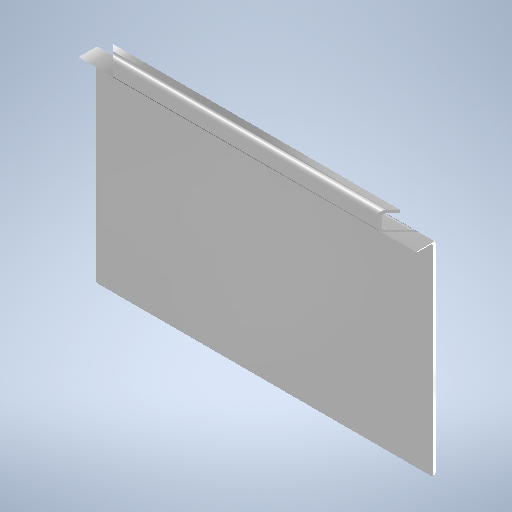
# Autodesk Inventor part: CHAPA 18 DE ACO INOX-304 - TAMPA DE FECHAMENTO DA CAIXA
Saved by Autodesk Inventor 2025 (Build 290162000, 162)
## iProperties
Created: 2019-07-12
Part Number: CHAPA 18 DE ACO INOX-304 - TAMPA DE FECHAMENTO DA CAIXA
Material: Aço inoxidável AISI 304
Document SubType Name: Chapa
Designer: CESAR
Density: 8 g/cm^3
Flat Pattern Width: 10.8343 cm
Flat Pattern Length: 14.88 cm
Flat Pattern Area: 161.214 cm^2
Sheet Metal Rule: Default_mm
Sheet Metal Width: 108,343 mm
Sheet Metal Length: 148,800 mm
Sheet Metal Area: 16121,440 mm^2
Appearance: Cromo - Acetinado
Mass: 609.333 g
Surface Area: 1281.93 cm^2
Volume: 76.1666 cm^3
Author: CESAR
Autodesk Inventor part; units mm, degrees
ref_plane "YZ Plane" through (0, 0, 0) normal (1, 0, 0) x (0, 1, 0)
ref_plane "XZ Plane" through (0, 0, 0) normal (0, 1, 0) x (-1, 0, 0)
ref_plane "XY Plane" through (0, 0, 0) normal (0, 0, 1) x (1, 0, 0)
sketch "Esboço1" plane through (0, 0, 0) normal (0, 1, 0) x (-1, 0, 0)
  line L0 (-74.4, 44.7) -> (74.4, 44.7)
  line L1 (74.4, 44.7) -> (74.4, -44.7)
  line L2 (74.4, -44.7) -> (-74.4, -44.7)
  line L3 (-74.4, -44.7) -> (-74.4, 44.7)
  line L4 (-74.4, 44.7) -> (74.4, -44.7) construction
  line L5 (74.4, 44.7) -> (-74.4, -44.7) construction
  point P0 (0, 0)
  dimension "d0" = 148.8
  dimension "d1" = 89.4
  measures "d0" distance of L1.end L2.end
  measures "d1" distance of L0.end L1.end
extrude "Placa1" add sketch "Esboço1" along normal blind 1.2
sketch "Esboço2" plane through (-74.4, 0, 44.7) normal (0, 0, 1) x (1, 0, 0)
  line L0 (148.8, 0) -> (0, 0)
  line L1 (0, 0) -> (0, -7.5)
  line L2 (0, -7.5) -> (148.8, -7.5)
  line L3 (148.8, -7.5) -> (148.8, 0)
  constraints: 4 end point, 4 other
edge flange "Flange1" height 7.5 angle 90 thickness 1.2 bend radius 1.2 thickness toward (0, 0, 1) relief tear relief width 1.2 relief depth 0.6 edges at (0, 0, 44.7) wall of the first edge with corners at (74.4, 0, 44.7) (-74.4, 0, 44.7) (-74.4, -7.5, 44.7) (74.4, -7.5, 44.7)
bend "Dobra1"
corner "Canto1"
sketch "Esboço3" plane through (74.4, -7.5, 45.9) normal (0, -1, 0) x (1, 0, 0)
  line L0 (-148.8, 0) -> (0, 0)
  line L1 (0, 0) -> (0, 6.5)
  line L2 (0, 6.5) -> (-148.8, 6.5)
  line L3 (-148.8, 6.5) -> (-148.8, 0)
  constraints: 4 end point, 4 other
edge flange "Flange2" height 6.5 angle 90 thickness 1.2 bend radius 1.2 thickness toward (0, -1, 0) relief tear relief width 1.2 relief depth 0.6 edges at (0, -7.5, 45.9) wall of the first edge with corners at (-74.4, -7.5, 45.9) (74.4, -7.5, 45.9) (74.4, -7.5, 52.4) (-74.4, -7.5, 52.4)
bend "Dobra2"
corner "Canto2"
sketch "Esboço4" plane through (74.4, -7.5, 52.4) normal (0, 0, 1) x (1, 0, 0)
  line L0 (-148.8, 0) -> (0, 0)
  line L1 (0, 0) -> (0, 4)
  line L2 (0, 4) -> (-148.8, 4)
  line L3 (-148.8, 4) -> (-148.8, 0)
  constraints: 4 end point, 4 other
edge flange "Flange3" height 4 angle 90 thickness 1.2 bend radius 1.2 thickness toward (0, 0, 1) relief tear relief width 1.2 relief depth 0.6 edges at (0, -7.5, 52.4) wall of the first edge with corners at (-74.4, -7.5, 52.4) (74.4, -7.5, 52.4) (74.4, -3.5, 52.4) (-74.4, -3.5, 52.4)
bend "Dobra3"
corner "Canto3"
fillet "Arredondamento de canto1" radius 1 2 edges at (74.4, 0.6, -44.7) (-74.4, 0.6, -44.7)
sketch "Esboço5" plane through (-74.4, -3.5, 53.6) normal (0, 0, 1) x (1, 0, 0)
  line L0 (0, 11) -> (0, -5.2)
  line L1 (0, -5.2) -> (16.2, -5.2)
  line L2 (16.2, -5.2) -> (0, 11)
  line L3 (148.8, -5.2) -> (0, -5.2) projected
  line L4 (148.8, 3.5) -> (0, 3.5) projected
  line L5 (74.4, 3.5) -> (74.4, -5.2) construction
  line L6 (148.8, 11) -> (148.8, -5.2)
  line L7 (148.8, -5.2) -> (132.6, -5.2)
  line L8 (132.6, -5.2) -> (148.8, 11)
  point P0 (148.8, 3.5)
  dimension "d34" = 16.2
  constraints: 14 end point, 3 symmetric about line, 2 perpendicular, 1 midpoint, 1 vertical
  measures "d34" distance of L0.end L0.start
extrude "Extrusão1" cut sketch "Esboço5" against normal blind 8.5 contours L2 L4 L0 | L4 L2 L1 L0 | L8 L6 L4 | L4 L6 L3 L8
equation "\"d37\" = Espessura"
equation "\"d3\" = Largura_alívio_de_dobra"
equation "\"d4\" = Profundidade_alívio_de_dobra"
equation "\"d5\" = Remanescente_mínimo"
equation "\"d6\" = Raio_dobra"
equation "\"d9\" = Raio_dobra"
equation "\"d10\" = Tamanho_alívio_de_dobra"
equation "\"d11\" = TamanhoFolga"
equation "\"d12\" = Tamanho_de_raio_de_Jacobi"
equation "\"d13\" = Largura_alívio_de_dobra"
equation "\"d14\" = Profundidade_alívio_de_dobra"
equation "\"d15\" = Remanescente_mínimo"
equation "\"d16\" = Raio_dobra"
equation "\"d19\" = Raio_dobra"
equation "\"d20\" = Tamanho_alívio_de_dobra"
equation "\"d21\" = TamanhoFolga"
equation "\"d22\" = Tamanho_de_raio_de_Jacobi"
equation "\"d23\" = Largura_alívio_de_dobra"
equation "\"d24\" = Profundidade_alívio_de_dobra"
equation "\"d25\" = Remanescente_mínimo"
equation "\"d26\" = Raio_dobra"
equation "\"d29\" = Raio_dobra"
equation "\"d30\" = Tamanho_alívio_de_dobra"
equation "\"d31\" = TamanhoFolga"
equation "\"d32\" = Tamanho_de_raio_de_Jacobi"
equation "\"Raio_dobra\" = Espessura"
equation "\"Largura_alívio_de_dobra\" = Espessura"
equation "\"Profundidade_alívio_de_dobra\" = 0.5 * Espessura"
equation "\"Tamanho_alívio_de_dobra\" = 4 * Espessura"
equation "\"Remanescente_mínimo\" = 2 * Espessura"
equation "\"Raiodetransição\" = Raio_dobra"
equation "\"Tamanho_de_raio_de_Jacobi\" = Raio_dobra"
equation "\"TamanhoFolga\" = Espessura"
equation "\"d2\" = Raio_dobra"
equation "\"Espessura\" = 1.2"
